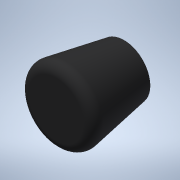
# Autodesk Inventor part: SP36V1 Pata Goma Freno
Saved by Autodesk Inventor 2021.2 (Build 252289000, 289)
## iProperties
Created: 2026-10-13
Part Number: SP36V1 Pata Goma Freno
Material: Rubber
Document SubType Name: Modeling
Designer: nelso
Density: 0.93 g/cm^3
Appearance: Rubber - Black
Author: nelso
Autodesk Inventor part; units mm, degrees
ref_plane "YZ Plane" through (0, 0, 0) normal (1, 0, 0) x (0, 1, 0)
ref_plane "XZ Plane" through (0, 0, 0) normal (0, 1, 0) x (-1, 0, 0)
ref_plane "XY Plane" through (0, 0, 0) normal (0, 0, 1) x (1, 0, 0)
sketch "Sketch1" plane through (0, 0, 0) normal (0, 1, 0) x (-1, 0, 0)
  circle A0 centre (0, 0) radius 7.25
  circle A1 centre (0, 0) radius 8.5
  dimension "d0" = 14.5
  dimension "d1" = 17
  constraints: 2 centre point, 2 coincident
  measures "d0" diameter of A0
  measures "d1" diameter of A1
extrude "Extrusion1" add sketch "Sketch1" against normal blind 22 draft 10 contours A0 | A1
fillet "Fillet1" radius 3 1 edges at (12.3792, -22, 0)
extrude "Extrusion2" cut sketch "Sketch1" against normal blind 15 contours A0
body "Solid1"
